Autodesk Fusion 360 part; units mm, degrees
(part 9 of 9)
equation "d2764 = ( ( ( ( ( 115 mm ) - holderStemX ) + ( 2.5 mm ) - 0.5 mm ) - 0.1 mm ) + ( 1.2 mm ) ) - ( ( ( ( 115 mm ) - holderStemX ) + ( 2.5 mm ) - 0.5 mm ) - 0.1 mm )"
equation "d2765 = ( ( ( ( ( ( keyRowOne ) - holderStemY ) - 1.2 mm ) - 2 mm ) + faceOriginV ) + ( 4 mm ) ) - ( ( ( ( ( keyRowOne ) - holderStemY ) - 1.2 mm ) - 2 mm ) + faceOriginV )"
equation "d2766 = rearHeight"
equation "compactTrialX = 145 mm" comment "Separate V2 coupon center"
equation "compactGuideClearance = 0.2 mm" comment "Radial clearance in STL 0.95 mm side notches"
equation "compactGuideHeight = 3 mm" comment "Guide within 3.2 mm notched region"
equation "compactStopWidth = 1.8 mm" comment "Wider upper stops for physical test"
equation "compactWireDiameter = 1.5 mm" comment "Provisional through-wall wire routing diameter"
equation "d2773 = compactTrialX - 11 mm"
equation "d2774 = ( keyRowOne - 11 mm ) + faceOriginV"
equation "d2775 = ( ( compactTrialX - 11 mm ) + ( 22 mm ) ) - ( compactTrialX - 11 mm )"
equation "d2776 = ( ( ( keyRowOne - 11 mm ) + faceOriginV ) + ( 22 mm ) ) - ( ( keyRowOne - 11 mm ) + faceOriginV )"
equation "d2777 = -( carrierThickness )"
equation "d2779 = compactTrialX - switchOpening / 2"
equation "d2780 = ( keyRowOne - switchOpening / 2 ) + faceOriginV"
equation "d2781 = ( ( compactTrialX - switchOpening / 2 ) + ( switchOpening ) ) - ( compactTrialX - switchOpening / 2 )"
equation "d2782 = ( ( ( keyRowOne - switchOpening / 2 ) + faceOriginV ) + ( switchOpening ) ) - ( ( keyRowOne - switchOpening / 2 ) + faceOriginV )"
equation "d2783 = -( carrierThickness + 0.1 mm )"
equation "d2785 = compactTrialX - holderFrameX / 2"
equation "d2786 = ( keyRowOne - holderFrameY / 2 ) + faceOriginV"
equation "d2787 = ( ( compactTrialX - holderFrameX / 2 ) + ( holderFrameX ) ) - ( compactTrialX - holderFrameX / 2 )"
equation "d2788 = ( ( ( keyRowOne - holderFrameY / 2 ) + faceOriginV ) + ( holderFrameY ) ) - ( ( keyRowOne - holderFrameY / 2 ) + faceOriginV )"
equation "d2789 = -( holderBottomDepth - shellWall - carrierClearance - carrierThickness )"
equation "d2791 = compactTrialX - holderSwitchVoid / 2"
equation "d2792 = ( keyRowOne - holderSwitchVoid / 2 ) + faceOriginV"
equation "d2793 = ( ( compactTrialX - holderSwitchVoid / 2 ) + ( holderSwitchVoid ) ) - ( compactTrialX - holderSwitchVoid / 2 )"
equation "d2794 = ( ( ( keyRowOne - holderSwitchVoid / 2 ) + faceOriginV ) + ( holderSwitchVoid ) ) - ( ( keyRowOne - holderSwitchVoid / 2 ) + faceOriginV )"
equation "d2795 = -( holderTopDepth - shellWall - carrierClearance - carrierThickness )"
equation "d2797 = compactTrialX - 5.42601681 mm - holderFit"
equation "d2798 = ( keyRowOne - 6.37220383 mm - holderFit ) + faceOriginV"
equation "d2799 = ( ( compactTrialX - 5.42601681 mm - holderFit ) + ( 11.03147984 mm + 2 * holderFit ) ) - ( compactTrialX - 5.42601681 mm - holderFit )"
equation "d2800 = ( ( ( keyRowOne - 6.37220383 mm - holderFit ) + faceOriginV ) + ( 9.74910235 mm + 2 * holderFit ) ) - ( ( keyRowOne - 6.37220383 mm - holderFit ) + faceOriginV )"
equation "d2801 = -( holderHeight + 0.1 mm )"
equation "d2803 = compactTrialX + ( -1 * 3 mm ) - compactStopWidth / 2"
equation "d2804 = ( keyRowOne + 2.6 mm ) + faceOriginV"
equation "d2805 = ( ( compactTrialX + ( -1 * 3 mm ) - compactStopWidth / 2 ) + ( compactStopWidth ) ) - ( compactTrialX + ( -1 * 3 mm ) - compactStopWidth / 2 )"
equation "d2806 = ( ( ( keyRowOne + 2.6 mm ) + faceOriginV ) + ( holderFrameY / 2 - 2.6 mm ) ) - ( ( keyRowOne + 2.6 mm ) + faceOriginV )"
equation "d2809 = compactTrialX - holderFrameX / 2"
equation "d2810 = ( keyRowOne - 0.35 mm ) + faceOriginV"
equation "d2811 = ( ( compactTrialX - holderFrameX / 2 ) + ( holderFrameX / 2 - 4.8 mm ) ) - ( compactTrialX - holderFrameX / 2 )"
equation "d2812 = ( ( ( keyRowOne - 0.35 mm ) + faceOriginV ) + ( 0.7 mm ) ) - ( ( keyRowOne - 0.35 mm ) + faceOriginV )"
equation "d2813 = compactGuideHeight"
equation "d2815 = compactTrialX + ( -1 * 4.8 mm )"
equation "d2816 = ( keyRowOne ) + faceOriginV"
equation "d2817 = 2 * ( 0.95 mm - compactGuideClearance )"
equation "d2818 = compactGuideHeight"
equation "d2820 = compactTrialX + ( 1 * 3 mm ) - compactStopWidth / 2"
equation "d2821 = ( keyRowOne + 2.6 mm ) + faceOriginV"
equation "d2822 = ( ( compactTrialX + ( 1 * 3 mm ) - compactStopWidth / 2 ) + ( compactStopWidth ) ) - ( compactTrialX + ( 1 * 3 mm ) - compactStopWidth / 2 )"
equation "d2823 = ( ( ( keyRowOne + 2.6 mm ) + faceOriginV ) + ( holderFrameY / 2 - 2.6 mm ) ) - ( ( keyRowOne + 2.6 mm ) + faceOriginV )"
equation "d2826 = compactTrialX + 4.8 mm"
equation "d2827 = ( keyRowOne - 0.35 mm ) + faceOriginV"
equation "d2828 = ( ( compactTrialX + 4.8 mm ) + ( holderFrameX / 2 - 4.8 mm ) ) - ( compactTrialX + 4.8 mm )"
equation "d2829 = ( ( ( keyRowOne - 0.35 mm ) + faceOriginV ) + ( 0.7 mm ) ) - ( ( keyRowOne - 0.35 mm ) + faceOriginV )"
equation "d2830 = compactGuideHeight"
equation "d2832 = compactTrialX + ( 1 * 4.8 mm )"
equation "d2833 = ( keyRowOne ) + faceOriginV"
equation "d2834 = 2 * ( 0.95 mm - compactGuideClearance )"
equation "d2835 = compactGuideHeight"
equation "d2837 = compactTrialX - 10 mm"
equation "d2839 = -( -1.7062782001271268 cm )"
equation "d2841 = compactWireDiameter"
equation "d2844 = -( -1.68700663682872 cm )"
equation "d2846 = compactWireDiameter"
equation "d2849 = -( -1.9961218786424535 cm )"
equation "d2851 = compactWireDiameter"
equation "d2854 = caseTilt"
equation "d2856 = 1 * ( keyRowOne + 10 mm + frontHeight * sin(caseTilt) )"
equation "d2859 = -( -1.7982695244660625 cm )"
equation "d2860 = compactWireDiameter"
equation "d2861 = -( 20 mm )"
named bodies: "UpperShell_Draft", "MiddleCarrier_Draft", "BottomCover_Draft", "Diffuser_Draft", "SwitchFitCoupon_Trial", "LidSupportCoupon_Trial", "SwitchFitCoupon_Compact_V2"
